Autodesk Fusion 360 part; units mm, degrees
(part 3 of 3)
component "Service_partition" placed x (1, 0, 0) y (0, 1, 0) z (0, 0, 1) at (0, 0, 0)
component "Service_floor" placed x (1, 0, 0) y (0, 1, 0) z (0, 0, 1) at (0, 0, 0)
component "Brace_lower" placed x (1, 0, 0) y (0, 1, 0) z (0, 0, 1) at (0, 0, 0)
component "Port_round_candidate" placed x (1, 0, 0) y (0, 1, 0) z (0, 0, 1) at (0, 0, 0)
component "REF_Faital_10FE200_4ohm_DATASHEET_ENVELOPE" placed x (1, 0, 0) y (0, 1, 0) z (0, 0, 1) at (0, 0, 0)
component "REF_BC_ME10V3_DATASHEET_ENVELOPE" placed x (1, 0, 0) y (0, 1, 0) z (0, 0, 1) at (0, 0, 0)
component "REF_BC_DE10_DATASHEET_ENVELOPE" placed x (1, 0, 0) y (0, 1, 0) z (0, 0, 1) at (0, 0, 0)
component "RESERVE_amp_wiring_UNVERIFIED_no_mounting_holes" placed x (1, 0, 0) y (0, 1, 0) z (0, 0, 1) at (0, 0, 0)
component "Rear_thread_plate_left_0.15" placed x (1, 0, 0) y (0, 1, 0) z (0, 0, 1) at (0, 0, 0)
component "Rear_thread_plate_left_0.5" placed x (1, 0, 0) y (0, 1, 0) z (0, 0, 1) at (0, 0, 0)
component "Rear_thread_plate_left_0.85" placed x (1, 0, 0) y (0, 1, 0) z (0, 0, 1) at (0, 0, 0)
component "Rear_thread_plate_right_0.15" placed x (1, 0, 0) y (0, 1, 0) z (0, 0, 1) at (0, 0, 0)
component "Rear_thread_plate_right_0.5" placed x (1, 0, 0) y (0, 1, 0) z (0, 0, 1) at (0, 0, 0)
component "Rear_thread_plate_right_0.85" placed x (1, 0, 0) y (0, 1, 0) z (0, 0, 1) at (0, 0, 0)
component "Rear_thread_plate_bottom_0.27" placed x (1, 0, 0) y (0, 1, 0) z (0, 0, 1) at (0, 0, 0)
component "Rear_thread_plate_bottom_0.73" placed x (1, 0, 0) y (0, 1, 0) z (0, 0, 1) at (0, 0, 0)
component "Rear_thread_plate_top_0.27" placed x (1, 0, 0) y (0, 1, 0) z (0, 0, 1) at (0, 0, 0)
component "Rear_thread_plate_top_0.73" placed x (1, 0, 0) y (0, 1, 0) z (0, 0, 1) at (0, 0, 0)
equation "height = 560 mm" comment "report:p12; envelope_not_CAD"
equation "width = 330 mm" comment "report:p12; envelope_not_CAD"
equation "depth = 300 mm" comment "report:p12; envelope_not_CAD"
equation "wall = 12 mm" comment "report:p12; design_candidate"
equation "lf_outer = 256.8 mm" comment "S31; design_candidate"
equation "lf_cutout = 233.3 mm" comment "S31; design_candidate"
equation "lf_depth = 102 mm" comment "S31; design_candidate"
equation "lf_flange = 8 mm" comment "S31; design_candidate"
equation "lf_pcd = 243.8 mm" comment "S31; design_candidate"
equation "lf_magnet_d = 115.3 mm" comment "S31:drawing_4; design_candidate"
equation "lf_magnet_depth = 34.7 mm" comment "S31:drawing_4; design_candidate"
equation "lf_basket_d = 231.8 mm" comment "S31:drawing_4; design_candidate"
equation "lf_hole_d = 5.7 mm" comment "S31:drawing_4; design_candidate"
equation "horn_width = 130.5 mm" comment "S50; design_candidate"
equation "horn_depth = 90 mm" comment "S50; design_candidate"
equation "horn_cutout = 104 mm" comment "S50:cutout_shape_to_verify; design_candidate"
equation "horn_throat = 25 mm" comment "S50; design_candidate"
equation "horn_flange = 5.5 mm" comment "S50:drawing_me10v3; manufacturer_dimension"
equation "hf_diameter = 90 mm" comment "S48; design_candidate"
equation "hf_depth = 53 mm" comment "S48; design_candidate"
equation "lf_y = 260 mm" comment "engineering:E02; design_candidate"
equation "horn_y = 470 mm" comment "engineering:E02; design_candidate"
equation "port_y = 70 mm" comment "engineering:E02; design_candidate"
equation "port_wall = 3 mm" comment "engineering:E02; design_candidate"
equation "service_floor_y = 350 mm" comment "engineering:E02; design_candidate"
equation "brace_y = 140 mm" comment "engineering:E02; design_candidate"
equation "brace_z = 200 mm" comment "engineering:E02; design_candidate"
equation "brace_height = 20 mm" comment "engineering:E02; design_candidate"
equation "baffle_clearance = 0.5 mm" comment "engineering:E02; radial_manufacturing_allowance"
equation "amp_reserve_width = 110 mm" comment "engineering:E02; unverified_installation_reserve_not_board_dimension"
equation "amp_reserve_height = 110 mm" comment "engineering:E02; unverified_installation_reserve_not_board_dimension"
equation "amp_reserve_depth = 40 mm" comment "engineering:E02; unverified_installation_reserve_not_board_dimension"
equation "rear_cleat_width = 20 mm" comment "engineering:E03; prototype_candidate_not_structurally_validated"
equation "rear_cleat_depth = 20 mm" comment "engineering:E03; prototype_candidate_not_structurally_validated"
equation "lf_backing_outer_d = 280 mm" comment "engineering:E03; prototype_candidate_not_structurally_validated"
equation "lf_backing_thickness = 3 mm" comment "engineering:E03; prototype_candidate_not_structurally_validated"
equation "lf_bolt_clearance = 5.5 mm" comment "engineering:E03; prototype_candidate_not_structurally_validated"
equation "horn_bolt_clearance = 4.5 mm" comment "engineering:E03; prototype_candidate_not_structurally_validated"
equation "horn_bolt_pitch = 114 mm" comment "S50:drawing_me10v3; manufacturer_dimension"
equation "port_backing_relief = 1 mm" comment "engineering:E03; prototype_candidate_not_structurally_validated"
equation "rear_bolt_clearance = 5.5 mm" comment "engineering:E03; prototype_candidate_not_structurally_validated"
equation "target_net = 34000000 mm^3" comment "report:p7"
equation "port_area = 6500 mm^2" comment "report:p7"
equation "port_length = 161.47860433 mm" comment "derived Helmholtz and equivalent-round end correction; prototype tune"
equation "lf_displacement = 600000 mm^3" comment "manufacturer occupied air volume, not solid clearance-envelope volume"
equation "horn_displacement = 150000 mm^3" comment "manufacturer horn volume"
equation "reinforcement_displacement = 1227503.1705 mm^3" comment "Python-derived E03 displacement"
equation "cleat_acoustic_displacement = 376800 mm^3" comment "Python-derived E03 displacement"
equation "backing_displacement = 70115.6356391 mm^3" comment "Python-derived E03 displacement"
equation "port_d = 90.9728368293 mm" comment "derived in Python; Fusion area-reference scaling workaround"
equation "service_z = 165.901490847 mm" comment "derived net-volume budget in Python; regenerate after dimensional changes"
equation "inner_width = width - 2 * wall" comment "E03 concept"
equation "inner_height = height - 2 * wall" comment "E03 concept"
equation "inner_depth = depth - 2 * wall" comment "E03 concept"
equation "port_outer_d = port_d + 2 * port_wall" comment "E03 concept"
equation "gross_internal = inner_width * inner_height * inner_depth" comment "E03 concept"
equation "port_displacement = PI / 4 * port_outer_d ^ 2 * ( port_length - 2 * wall )" comment "E03 concept"
equation "hf_displacement = PI / 4 * hf_diameter ^ 2 * hf_depth" comment "E03 concept"
equation "brace_displacement = inner_width * brace_height * wall" comment "E03 concept"
equation "service_reserve = inner_width * ( height - wall - service_floor_y ) * ( depth - wall - service_z )" comment "E03 concept"
equation "d63 = wall"
equation "d64 = height"
equation "d65 = depth"
equation "d69 = width - wall"
equation "d70 = wall"
equation "d71 = height"
equation "d72 = depth"
equation "d76 = wall"
equation "d77 = inner_width"
equation "d78 = wall"
equation "d79 = depth"
equation "d83 = wall"
equation "d84 = height - wall"
equation "d85 = inner_width"
equation "d86 = wall"
equation "d87 = depth"
equation "d91 = wall"
equation "d92 = wall"
equation "d93 = inner_width"
equation "d94 = inner_height"
equation "d95 = wall"
equation "d97 = depth - wall"
equation "d99 = wall"
equation "d100 = wall"
equation "d101 = inner_width"
equation "d102 = inner_height"
equation "d103 = wall"
equation "d107 = width / 2"
equation "d108 = lf_y"
equation "d109 = lf_cutout + 2 * baffle_clearance"
equation "d110 = wall"
equation "d114 = width / 2"
equation "d115 = port_y"
equation "d116 = port_outer_d + 2 * baffle_clearance"
equation "d117 = wall"
equation "d121 = ( width - horn_cutout ) / 2"
equation "d122 = horn_y - horn_cutout / 2"
equation "d123 = horn_cutout"
equation "d124 = horn_cutout"
equation "d125 = wall"
equation "d127 = wall"
equation "d129 = wall"
equation "d130 = wall"
equation "d131 = inner_width"
equation "d132 = inner_height"
equation "d133 = wall"
equation "d135 = wall"
equation "d137 = width / 2"
equation "d138 = lf_y"
equation "d139 = lf_cutout + 2 * baffle_clearance"
equation "d140 = wall"
equation "d142 = wall"
equation "d144 = width / 2"
equation "d145 = port_y"
equation "d146 = port_outer_d + 2 * baffle_clearance"
equation "d147 = wall"
equation "d149 = wall"
equation "d151 = ( width - horn_cutout ) / 2"
equation "d152 = horn_y - horn_cutout / 2"
equation "d153 = horn_cutout"
equation "d154 = horn_cutout"
equation "d155 = wall"
equation "d159 = width / 2 + lf_pcd / 2 * ( 1 )"
equation "d160 = lf_y + lf_pcd / 2 * ( 0 )"
equation "d161 = lf_bolt_clearance"
equation "d162 = wall"
equation "d166 = width / 2 + lf_pcd / 2 * ( 0.707106781186548 )"
equation "d167 = lf_y + lf_pcd / 2 * ( 0.707106781186548 )"
equation "d168 = lf_bolt_clearance"
equation "d169 = wall"
equation "d173 = width / 2 + lf_pcd / 2 * ( 0.000 )"
equation "d174 = lf_y + lf_pcd / 2 * ( 1 )"
equation "d175 = lf_bolt_clearance"
equation "d176 = wall"
equation "d180 = width / 2 + lf_pcd / 2 * ( -0.707106781186547 )"
equation "d181 = lf_y + lf_pcd / 2 * ( 0.707106781186548 )"
equation "d182 = lf_bolt_clearance"
equation "d183 = wall"
equation "d187 = width / 2 + lf_pcd / 2 * ( -1 )"
equation "d188 = lf_y + lf_pcd / 2 * ( 0.000 )"
equation "d189 = lf_bolt_clearance"
equation "d190 = wall"
equation "d194 = width / 2 + lf_pcd / 2 * ( -0.707106781186548 )"
equation "d195 = lf_y + lf_pcd / 2 * ( -0.707106781186547 )"
equation "d196 = lf_bolt_clearance"
equation "d197 = wall"
equation "d201 = width / 2 + lf_pcd / 2 * ( -0.000 )"
equation "d202 = lf_y + lf_pcd / 2 * ( -1 )"
equation "d203 = lf_bolt_clearance"
equation "d204 = wall"
equation "d208 = width / 2 + lf_pcd / 2 * ( 0.707106781186547 )"
equation "d209 = lf_y + lf_pcd / 2 * ( -0.707106781186548 )"
equation "d210 = lf_bolt_clearance"
equation "d211 = wall"
equation "d215 = width / 2 + ( -1 ) * horn_bolt_pitch / 2"
equation "d216 = horn_y + ( -1 ) * horn_bolt_pitch / 2"
equation "d217 = horn_bolt_clearance"
equation "d218 = wall"
equation "d222 = width / 2 + ( -1 ) * horn_bolt_pitch / 2"
equation "d223 = horn_y + ( 1 ) * horn_bolt_pitch / 2"
equation "d224 = horn_bolt_clearance"
equation "d225 = wall"
equation "d229 = width / 2 + ( 1 ) * horn_bolt_pitch / 2"
equation "d230 = horn_y + ( -1 ) * horn_bolt_pitch / 2"
equation "d231 = horn_bolt_clearance"
equation "d232 = wall"
equation "d236 = width / 2 + ( 1 ) * horn_bolt_pitch / 2"
equation "d237 = horn_y + ( 1 ) * horn_bolt_pitch / 2"
equation "d238 = horn_bolt_clearance"
equation "d239 = wall"
equation "d241 = wall"
equation "d243 = width / 2 + lf_pcd / 2 * ( 1 )"
equation "d244 = lf_y + lf_pcd / 2 * ( 0 )"
equation "d245 = lf_bolt_clearance"
equation "d246 = wall"
equation "d248 = wall"
equation "d250 = width / 2 + lf_pcd / 2 * ( 0.707106781186548 )"
equation "d251 = lf_y + lf_pcd / 2 * ( 0.707106781186548 )"
equation "d252 = lf_bolt_clearance"
equation "d253 = wall"
equation "d255 = wall"
equation "d257 = width / 2 + lf_pcd / 2 * ( 0.000 )"
equation "d258 = lf_y + lf_pcd / 2 * ( 1 )"
equation "d259 = lf_bolt_clearance"
equation "d260 = wall"
equation "d262 = wall"
equation "d264 = width / 2 + lf_pcd / 2 * ( -0.707106781186547 )"
equation "d265 = lf_y + lf_pcd / 2 * ( 0.707106781186548 )"
equation "d266 = lf_bolt_clearance"
equation "d267 = wall"
equation "d269 = wall"
equation "d271 = width / 2 + lf_pcd / 2 * ( -1 )"
equation "d272 = lf_y + lf_pcd / 2 * ( 0.000 )"
equation "d273 = lf_bolt_clearance"
equation "d274 = wall"
equation "d276 = wall"
equation "d278 = width / 2 + lf_pcd / 2 * ( -0.707106781186548 )"
equation "d279 = lf_y + lf_pcd / 2 * ( -0.707106781186547 )"
equation "d280 = lf_bolt_clearance"
equation "d281 = wall"
equation "d283 = wall"
equation "d285 = width / 2 + lf_pcd / 2 * ( -0.000 )"
equation "d286 = lf_y + lf_pcd / 2 * ( -1 )"
equation "d287 = lf_bolt_clearance"
equation "d288 = wall"
equation "d290 = wall"
equation "d292 = width / 2 + lf_pcd / 2 * ( 0.707106781186547 )"
equation "d293 = lf_y + lf_pcd / 2 * ( -0.707106781186548 )"
equation "d294 = lf_bolt_clearance"
equation "d295 = wall"
equation "d297 = wall"
equation "d299 = width / 2 + ( -1 ) * horn_bolt_pitch / 2"
equation "d300 = horn_y + ( -1 ) * horn_bolt_pitch / 2"
equation "d301 = horn_bolt_clearance"
equation "d302 = wall"
equation "d304 = wall"
equation "d306 = width / 2 + ( -1 ) * horn_bolt_pitch / 2"
equation "d307 = horn_y + ( 1 ) * horn_bolt_pitch / 2"
equation "d308 = horn_bolt_clearance"
equation "d309 = wall"
equation "d311 = wall"
equation "d313 = width / 2 + ( 1 ) * horn_bolt_pitch / 2"
equation "d314 = horn_y + ( -1 ) * horn_bolt_pitch / 2"
equation "d315 = horn_bolt_clearance"
equation "d316 = wall"
equation "d318 = wall"
equation "d320 = width / 2 + ( 1 ) * horn_bolt_pitch / 2"
equation "d321 = horn_y + ( 1 ) * horn_bolt_pitch / 2"
equation "d322 = horn_bolt_clearance"
equation "d323 = wall"
equation "d325 = 2 * wall"
equation "d327 = width / 2"
equation "d328 = lf_y"
equation "d329 = lf_backing_outer_d"
equation "d330 = lf_backing_inner_d"
equation "d331 = lf_backing_thickness"
equation "d333 = 2 * wall"
equation "d335 = width / 2"
equation "d336 = port_y"
equation "d337 = port_outer_d + 2 * port_backing_relief"
equation "d340 = 2 * wall"
equation "d342 = width / 2 + lf_pcd / 2 * ( 1 )"
equation "d343 = lf_y + lf_pcd / 2 * ( 0 )"
equation "d344 = lf_bolt_clearance"
equation "d345 = lf_backing_thickness"
equation "d347 = 2 * wall"
equation "d349 = width / 2 + lf_pcd / 2 * ( 0.707106781186548 )"
equation "d350 = lf_y + lf_pcd / 2 * ( 0.707106781186548 )"
equation "d351 = lf_bolt_clearance"
equation "d352 = lf_backing_thickness"
equation "d354 = 2 * wall"
equation "d356 = width / 2 + lf_pcd / 2 * ( 0.000 )"
equation "d357 = lf_y + lf_pcd / 2 * ( 1 )"
equation "d358 = lf_bolt_clearance"
equation "d359 = lf_backing_thickness"
equation "d361 = 2 * wall"
equation "d363 = width / 2 + lf_pcd / 2 * ( -0.707106781186547 )"
equation "d364 = lf_y + lf_pcd / 2 * ( 0.707106781186548 )"
equation "d365 = lf_bolt_clearance"
equation "d366 = lf_backing_thickness"
equation "d368 = 2 * wall"
equation "d370 = width / 2 + lf_pcd / 2 * ( -1 )"
equation "d371 = lf_y + lf_pcd / 2 * ( 0.000 )"
equation "d372 = lf_bolt_clearance"
equation "d373 = lf_backing_thickness"
equation "d375 = 2 * wall"
equation "d377 = width / 2 + lf_pcd / 2 * ( -0.707106781186548 )"
equation "d378 = lf_y + lf_pcd / 2 * ( -0.707106781186547 )"
equation "d379 = lf_bolt_clearance"
equation "d380 = lf_backing_thickness"
equation "d382 = 2 * wall"
equation "d384 = width / 2 + lf_pcd / 2 * ( -0.000 )"
equation "d385 = lf_y + lf_pcd / 2 * ( -1 )"
equation "d386 = lf_bolt_clearance"
equation "d387 = lf_backing_thickness"
equation "d389 = 2 * wall"
equation "d391 = width / 2 + lf_pcd / 2 * ( 0.707106781186547 )"
equation "d392 = lf_y + lf_pcd / 2 * ( -0.707106781186548 )"
equation "d393 = lf_bolt_clearance"
equation "d394 = lf_backing_thickness"
equation "d396 = depth - wall - rear_cleat_depth"
equation "d398 = wall"
equation "d399 = wall"
equation "d400 = rear_cleat_width"
equation "d401 = inner_height"
equation "d402 = rear_cleat_depth"
equation "d404 = depth - wall - rear_cleat_depth"
equation "d406 = width - wall - rear_cleat_width"
equation "d407 = wall"
equation "d408 = rear_cleat_width"
equation "d409 = inner_height"
equation "d410 = rear_cleat_depth"
equation "d412 = depth - wall - rear_cleat_depth"
equation "d414 = wall + rear_cleat_width"
equation "d415 = wall"
equation "d416 = inner_width - 2 * rear_cleat_width"
equation "d417 = rear_cleat_width"
equation "d418 = rear_cleat_depth"
equation "d420 = depth - wall - rear_cleat_depth"
equation "d422 = wall + rear_cleat_width"
equation "d423 = height - wall - rear_cleat_width"
equation "d424 = inner_width - 2 * rear_cleat_width"
equation "d425 = rear_cleat_width"
equation "d426 = rear_cleat_depth"
equation "d428 = service_z"
equation "d430 = wall"
equation "d431 = service_floor_y + wall"
equation "d432 = inner_width"
equation "d433 = height - wall - service_floor_y - wall"
equation "d434 = wall"
equation "d436 = service_z"
equation "d438 = wall"
equation "d439 = service_floor_y"
equation "d440 = inner_width"
equation "d441 = wall"
equation "d442 = depth - wall - service_z"
equation "d444 = brace_z"
equation "d446 = wall"
equation "d447 = brace_y"
equation "d448 = inner_width"
equation "d449 = brace_height"
equation "d450 = wall"
equation "d454 = width / 2"
equation "d455 = port_y"
equation "d456 = port_outer_d"
equation "d457 = port_d"
equation "d458 = port_length"
equation "d460 = -lf_flange"
equation "d462 = width / 2"
equation "d463 = lf_y"
equation "d464 = lf_outer"
equation "d465 = lf_cutout"
equation "d466 = lf_flange"
equation "d470 = width / 2"
equation "d471 = lf_y"
equation "d472 = lf_basket_d"
equation "d473 = lf_depth - lf_flange - lf_magnet_depth"
equation "d475 = width / 2"
equation "d476 = lf_y"
equation "d477 = lf_magnet_d"
equation "d478 = lf_depth - lf_flange - lf_magnet_depth"
equation "d480 = width / 2"
equation "d481 = lf_y"
equation "d482 = lf_magnet_d"
equation "d483 = lf_magnet_depth"
equation "d485 = -horn_flange"
equation "d487 = ( width - horn_width ) / 2"
equation "d488 = horn_y - horn_width / 2"
equation "d489 = horn_width"
equation "d490 = horn_width"
equation "d491 = horn_flange"
equation "d493 = -horn_flange"
equation "d495 = ( width - horn_cutout ) / 2"
equation "d496 = horn_y - horn_cutout / 2"
equation "d497 = horn_cutout"
equation "d498 = horn_cutout"
equation "d499 = horn_flange"
equation "d503 = ( width - horn_cutout ) / 2"
equation "d504 = horn_y - horn_cutout / 2"
equation "d505 = horn_cutout"
equation "d506 = horn_cutout"
equation "d507 = horn_depth - horn_flange"
equation "d509 = width / 2"
equation "d510 = horn_y"
equation "d511 = horn_throat"
equation "d512 = horn_depth - horn_flange"
equation "d514 = width / 2"
equation "d515 = horn_y"
equation "d516 = hf_diameter"
equation "d517 = hf_depth"
equation "d519 = service_z + wall + 10 mm"
equation "d521 = ( width - amp_reserve_width ) / 2"
equation "d522 = service_floor_y + wall + 10 mm"
equation "d523 = amp_reserve_width"
equation "d524 = amp_reserve_height"
equation "d525 = amp_reserve_depth"
equation "d527 = depth - wall - rear_cleat_depth"
equation "d533 = depth - wall - rear_cleat_depth"
equation "rear_plate_width = 20 mm" comment "engineering:E03_assembly"
equation "rear_plate_length = 40 mm" comment "engineering:E03_assembly"
equation "rear_plate_thickness = 5 mm" comment "engineering:E03_assembly"
equation "rear_tap_pilot = 4.2 mm" comment "engineering:E03_assembly"
equation "rear_retainer_bore = 3 mm" comment "engineering:E03_assembly"
equation "rear_retainer_pitch = 24 mm" comment "engineering:E03_assembly"
equation "gasket_groove_width = 4 mm" comment "engineering:E03_assembly"
equation "gasket_groove_depth = 1 mm" comment "engineering:E03_assembly"
equation "gasket_edge_offset = 2 mm" comment "engineering:E03_assembly"
equation "rear_fixing_displacement = 20309.2569506 mm^3" comment "Python-derived volume budget"
equation "d549 = depth - wall"
equation "d551 = wall + rear_cleat_width / 2"
equation "d552 = height * 0.15"
equation "d553 = rear_bolt_clearance"
equation "d554 = wall"
equation "d556 = depth - wall - rear_cleat_depth"
equation "d558 = wall + rear_cleat_width / 2"
equation "d559 = height * 0.15"
equation "d560 = rear_bolt_clearance"
equation "d563 = depth - wall - rear_cleat_depth - rear_plate_thickness"
equation "d565 = ( wall + rear_cleat_width / 2 ) - ( rear_plate_width ) / 2"
equation "d566 = ( height * 0.15 ) - ( rear_plate_length ) / 2"
equation "d567 = rear_plate_width"
equation "d568 = rear_plate_length"
equation "d569 = rear_plate_thickness"
equation "d571 = depth - wall - rear_cleat_depth - rear_plate_thickness"
equation "d573 = wall + rear_cleat_width / 2"
equation "d574 = height * 0.15"
equation "d575 = rear_tap_pilot"
equation "d576 = rear_plate_thickness"
equation "d578 = depth - wall - rear_cleat_depth - rear_plate_thickness"
equation "d580 = wall + rear_cleat_width / 2"
equation "d581 = ( height * 0.15 ) + ( -1 ) * rear_retainer_pitch / 2"
equation "d582 = rear_retainer_bore"
equation "d583 = rear_plate_thickness"
equation "d585 = depth - wall - rear_cleat_depth - rear_plate_thickness"
equation "d587 = wall + rear_cleat_width / 2"
equation "d588 = ( height * 0.15 ) + ( 1 ) * rear_retainer_pitch / 2"
equation "d589 = rear_retainer_bore"
equation "d590 = rear_plate_thickness"
equation "d592 = depth - wall"
equation "d594 = wall + rear_cleat_width / 2"
equation "d595 = height * 0.5"
equation "d596 = rear_bolt_clearance"
equation "d597 = wall"
equation "d599 = depth - wall - rear_cleat_depth"
equation "d601 = wall + rear_cleat_width / 2"
equation "d602 = height * 0.5"
equation "d603 = rear_bolt_clearance"
equation "d606 = depth - wall - rear_cleat_depth - rear_plate_thickness"
equation "d608 = ( wall + rear_cleat_width / 2 ) - ( rear_plate_width ) / 2"
equation "d609 = ( height * 0.5 ) - ( rear_plate_length ) / 2"
equation "d610 = rear_plate_width"
equation "d611 = rear_plate_length"
equation "d612 = rear_plate_thickness"
equation "d614 = depth - wall - rear_cleat_depth - rear_plate_thickness"
equation "d616 = wall + rear_cleat_width / 2"
equation "d617 = height * 0.5"
equation "d618 = rear_tap_pilot"
equation "d619 = rear_plate_thickness"
equation "d621 = depth - wall - rear_cleat_depth - rear_plate_thickness"
equation "d623 = wall + rear_cleat_width / 2"
equation "d624 = ( height * 0.5 ) + ( -1 ) * rear_retainer_pitch / 2"
equation "d625 = rear_retainer_bore"
equation "d626 = rear_plate_thickness"
equation "d628 = depth - wall - rear_cleat_depth - rear_plate_thickness"
equation "d630 = wall + rear_cleat_width / 2"
equation "d631 = ( height * 0.5 ) + ( 1 ) * rear_retainer_pitch / 2"
equation "d632 = rear_retainer_bore"
equation "d633 = rear_plate_thickness"
equation "d635 = depth - wall"
equation "d637 = wall + rear_cleat_width / 2"
equation "d638 = height * 0.85"
equation "d639 = rear_bolt_clearance"
equation "d640 = wall"
equation "d642 = depth - wall - rear_cleat_depth"
equation "d644 = wall + rear_cleat_width / 2"
equation "d645 = height * 0.85"
equation "d646 = rear_bolt_clearance"
equation "d649 = depth - wall - rear_cleat_depth - rear_plate_thickness"
equation "d651 = ( wall + rear_cleat_width / 2 ) - ( rear_plate_width ) / 2"
equation "d652 = ( height * 0.85 ) - ( rear_plate_length ) / 2"
equation "d653 = rear_plate_width"
equation "d654 = rear_plate_length"
equation "d655 = rear_plate_thickness"
equation "d657 = depth - wall - rear_cleat_depth - rear_plate_thickness"
equation "d659 = wall + rear_cleat_width / 2"
equation "d660 = height * 0.85"
equation "d661 = rear_tap_pilot"
equation "d662 = rear_plate_thickness"
equation "d664 = depth - wall - rear_cleat_depth - rear_plate_thickness"
equation "d666 = wall + rear_cleat_width / 2"
equation "d667 = ( height * 0.85 ) + ( -1 ) * rear_retainer_pitch / 2"
equation "d668 = rear_retainer_bore"
equation "d669 = rear_plate_thickness"
equation "d671 = depth - wall - rear_cleat_depth - rear_plate_thickness"
equation "d673 = wall + rear_cleat_width / 2"
equation "d674 = ( height * 0.85 ) + ( 1 ) * rear_retainer_pitch / 2"
equation "d675 = rear_retainer_bore"
equation "d676 = rear_plate_thickness"
equation "d678 = depth - wall"
equation "d680 = width - wall - rear_cleat_width / 2"
equation "d681 = height * 0.15"
equation "d682 = rear_bolt_clearance"
equation "d683 = wall"
equation "d685 = depth - wall - rear_cleat_depth"
equation "d687 = width - wall - rear_cleat_width / 2"
equation "d688 = height * 0.15"
equation "d689 = rear_bolt_clearance"
equation "d692 = depth - wall - rear_cleat_depth - rear_plate_thickness"
equation "d694 = ( width - wall - rear_cleat_width / 2 ) - ( rear_plate_width ) / 2"
equation "d695 = ( height * 0.15 ) - ( rear_plate_length ) / 2"
equation "d696 = rear_plate_width"
equation "d697 = rear_plate_length"
equation "d698 = rear_plate_thickness"
equation "d700 = depth - wall - rear_cleat_depth - rear_plate_thickness"
equation "d702 = width - wall - rear_cleat_width / 2"
equation "d703 = height * 0.15"
equation "d704 = rear_tap_pilot"
equation "d705 = rear_plate_thickness"
equation "d707 = depth - wall - rear_cleat_depth - rear_plate_thickness"
equation "d709 = width - wall - rear_cleat_width / 2"
equation "d710 = ( height * 0.15 ) + ( -1 ) * rear_retainer_pitch / 2"
equation "d711 = rear_retainer_bore"
equation "d712 = rear_plate_thickness"
equation "d714 = depth - wall - rear_cleat_depth - rear_plate_thickness"
equation "d716 = width - wall - rear_cleat_width / 2"
equation "d717 = ( height * 0.15 ) + ( 1 ) * rear_retainer_pitch / 2"
equation "d718 = rear_retainer_bore"
equation "d719 = rear_plate_thickness"
equation "d721 = depth - wall"
equation "d723 = width - wall - rear_cleat_width / 2"
equation "d724 = height * 0.5"
equation "d725 = rear_bolt_clearance"
equation "d726 = wall"
equation "d728 = depth - wall - rear_cleat_depth"
equation "d730 = width - wall - rear_cleat_width / 2"
equation "d731 = height * 0.5"
equation "d732 = rear_bolt_clearance"
equation "d735 = depth - wall - rear_cleat_depth - rear_plate_thickness"
equation "d737 = ( width - wall - rear_cleat_width / 2 ) - ( rear_plate_width ) / 2"
equation "d738 = ( height * 0.5 ) - ( rear_plate_length ) / 2"
equation "d739 = rear_plate_width"
equation "d740 = rear_plate_length"
equation "d741 = rear_plate_thickness"
equation "d743 = depth - wall - rear_cleat_depth - rear_plate_thickness"
equation "d745 = width - wall - rear_cleat_width / 2"
equation "d746 = height * 0.5"
equation "d747 = rear_tap_pilot"
equation "d748 = rear_plate_thickness"
equation "d750 = depth - wall - rear_cleat_depth - rear_plate_thickness"
equation "d752 = width - wall - rear_cleat_width / 2"
equation "d753 = ( height * 0.5 ) + ( -1 ) * rear_retainer_pitch / 2"
equation "d754 = rear_retainer_bore"
equation "d755 = rear_plate_thickness"
equation "d757 = depth - wall - rear_cleat_depth - rear_plate_thickness"
equation "d759 = width - wall - rear_cleat_width / 2"
equation "d760 = ( height * 0.5 ) + ( 1 ) * rear_retainer_pitch / 2"
equation "d761 = rear_retainer_bore"
equation "d762 = rear_plate_thickness"
equation "d764 = depth - wall"
equation "d766 = width - wall - rear_cleat_width / 2"
equation "d767 = height * 0.85"
equation "d768 = rear_bolt_clearance"
equation "d769 = wall"
equation "d771 = depth - wall - rear_cleat_depth"
equation "d773 = width - wall - rear_cleat_width / 2"
equation "d774 = height * 0.85"
equation "d775 = rear_bolt_clearance"
equation "d778 = depth - wall - rear_cleat_depth - rear_plate_thickness"
equation "d780 = ( width - wall - rear_cleat_width / 2 ) - ( rear_plate_width ) / 2"
equation "d781 = ( height * 0.85 ) - ( rear_plate_length ) / 2"
equation "d782 = rear_plate_width"
equation "d783 = rear_plate_length"
equation "d784 = rear_plate_thickness"
equation "d786 = depth - wall - rear_cleat_depth - rear_plate_thickness"
equation "d788 = width - wall - rear_cleat_width / 2"
equation "d789 = height * 0.85"
equation "d790 = rear_tap_pilot"
equation "d791 = rear_plate_thickness"
equation "d793 = depth - wall - rear_cleat_depth - rear_plate_thickness"
equation "d795 = width - wall - rear_cleat_width / 2"
equation "d796 = ( height * 0.85 ) + ( -1 ) * rear_retainer_pitch / 2"
equation "d797 = rear_retainer_bore"
equation "d798 = rear_plate_thickness"
equation "d800 = depth - wall - rear_cleat_depth - rear_plate_thickness"
equation "d802 = width - wall - rear_cleat_width / 2"
equation "d803 = ( height * 0.85 ) + ( 1 ) * rear_retainer_pitch / 2"
equation "d804 = rear_retainer_bore"
equation "d805 = rear_plate_thickness"
equation "d807 = depth - wall"
equation "d809 = width * 0.27"
equation "d810 = wall + rear_cleat_width / 2"
equation "d811 = rear_bolt_clearance"
equation "d812 = wall"
equation "d814 = depth - wall - rear_cleat_depth"
equation "d816 = width * 0.27"
equation "d817 = wall + rear_cleat_width / 2"
equation "d818 = rear_bolt_clearance"
equation "d819 = rear_cleat_depth"
equation "d821 = depth - wall - rear_cleat_depth - rear_plate_thickness"
equation "d823 = ( width * 0.27 ) - ( rear_plate_length ) / 2"
equation "d824 = ( wall + rear_cleat_width / 2 ) - ( rear_plate_width ) / 2"
equation "d825 = rear_plate_length"
equation "d826 = rear_plate_width"
equation "d827 = rear_plate_thickness"
equation "d829 = depth - wall - rear_cleat_depth - rear_plate_thickness"
equation "d831 = width * 0.27"
equation "d832 = wall + rear_cleat_width / 2"
equation "d833 = rear_tap_pilot"
equation "d834 = rear_plate_thickness"
equation "d836 = depth - wall - rear_cleat_depth - rear_plate_thickness"
equation "d838 = ( width * 0.27 ) + ( -1 ) * rear_retainer_pitch / 2"
equation "d839 = wall + rear_cleat_width / 2"
equation "d840 = rear_retainer_bore"
equation "d841 = rear_plate_thickness"
equation "d843 = depth - wall - rear_cleat_depth - rear_plate_thickness"
equation "d845 = ( width * 0.27 ) + ( 1 ) * rear_retainer_pitch / 2"
equation "d846 = wall + rear_cleat_width / 2"
equation "d847 = rear_retainer_bore"
equation "d848 = rear_plate_thickness"
equation "d850 = depth - wall"
equation "d852 = width * 0.73"
equation "d853 = wall + rear_cleat_width / 2"
equation "d854 = rear_bolt_clearance"
equation "d855 = wall"
equation "d857 = depth - wall - rear_cleat_depth"
equation "d859 = width * 0.73"
equation "d860 = wall + rear_cleat_width / 2"
equation "d861 = rear_bolt_clearance"
equation "d862 = rear_cleat_depth"
equation "d864 = depth - wall - rear_cleat_depth - rear_plate_thickness"
equation "d866 = ( width * 0.73 ) - ( rear_plate_length ) / 2"
equation "d867 = ( wall + rear_cleat_width / 2 ) - ( rear_plate_width ) / 2"
equation "d868 = rear_plate_length"
equation "d869 = rear_plate_width"
equation "d870 = rear_plate_thickness"
equation "d872 = depth - wall - rear_cleat_depth - rear_plate_thickness"
equation "d874 = width * 0.73"
equation "d875 = wall + rear_cleat_width / 2"
equation "d876 = rear_tap_pilot"
equation "d877 = rear_plate_thickness"
equation "d879 = depth - wall - rear_cleat_depth - rear_plate_thickness"
equation "d881 = ( width * 0.73 ) + ( -1 ) * rear_retainer_pitch / 2"
equation "d882 = wall + rear_cleat_width / 2"
equation "d883 = rear_retainer_bore"
equation "d884 = rear_plate_thickness"
equation "d886 = depth - wall - rear_cleat_depth - rear_plate_thickness"
equation "d888 = ( width * 0.73 ) + ( 1 ) * rear_retainer_pitch / 2"
equation "d889 = wall + rear_cleat_width / 2"
equation "d890 = rear_retainer_bore"
equation "d891 = rear_plate_thickness"
equation "d893 = depth - wall"
equation "d895 = width * 0.27"
equation "d896 = height - wall - rear_cleat_width / 2"
equation "d897 = rear_bolt_clearance"
equation "d898 = wall"
equation "d900 = depth - wall - rear_cleat_depth"
equation "d902 = width * 0.27"
equation "d903 = height - wall - rear_cleat_width / 2"
equation "d904 = rear_bolt_clearance"
equation "d905 = rear_cleat_depth"
equation "d907 = depth - wall - rear_cleat_depth - rear_plate_thickness"
equation "d909 = ( width * 0.27 ) - ( rear_plate_length ) / 2"
equation "d910 = ( height - wall - rear_cleat_width / 2 ) - ( rear_plate_width ) / 2"
equation "d911 = rear_plate_length"
equation "d912 = rear_plate_width"
equation "d913 = rear_plate_thickness"
equation "d915 = depth - wall - rear_cleat_depth - rear_plate_thickness"
equation "d917 = width * 0.27"
equation "d918 = height - wall - rear_cleat_width / 2"
equation "d919 = rear_tap_pilot"
equation "d920 = rear_plate_thickness"
equation "d922 = depth - wall - rear_cleat_depth - rear_plate_thickness"
equation "d924 = ( width * 0.27 ) + ( -1 ) * rear_retainer_pitch / 2"
equation "d925 = height - wall - rear_cleat_width / 2"
equation "d926 = rear_retainer_bore"
equation "d927 = rear_plate_thickness"
equation "d929 = depth - wall - rear_cleat_depth - rear_plate_thickness"
equation "d931 = ( width * 0.27 ) + ( 1 ) * rear_retainer_pitch / 2"
equation "d932 = height - wall - rear_cleat_width / 2"
equation "d933 = rear_retainer_bore"
equation "d934 = rear_plate_thickness"
equation "d936 = depth - wall"
equation "d938 = width * 0.73"
equation "d939 = height - wall - rear_cleat_width / 2"
equation "d940 = rear_bolt_clearance"
equation "d941 = wall"
equation "d943 = depth - wall - rear_cleat_depth"
equation "d945 = width * 0.73"
equation "d946 = height - wall - rear_cleat_width / 2"
equation "d947 = rear_bolt_clearance"
equation "d948 = rear_cleat_depth"
equation "d950 = depth - wall - rear_cleat_depth - rear_plate_thickness"
equation "d952 = ( width * 0.73 ) - ( rear_plate_length ) / 2"
equation "d953 = ( height - wall - rear_cleat_width / 2 ) - ( rear_plate_width ) / 2"
equation "d954 = rear_plate_length"
equation "d955 = rear_plate_width"
equation "d956 = rear_plate_thickness"
equation "d958 = depth - wall - rear_cleat_depth - rear_plate_thickness"
equation "d960 = width * 0.73"
equation "d961 = height - wall - rear_cleat_width / 2"
equation "d962 = rear_tap_pilot"
equation "d963 = rear_plate_thickness"
equation "d965 = depth - wall - rear_cleat_depth - rear_plate_thickness"
equation "d967 = ( width * 0.73 ) + ( -1 ) * rear_retainer_pitch / 2"
equation "d968 = height - wall - rear_cleat_width / 2"
equation "d969 = rear_retainer_bore"
equation "d970 = rear_plate_thickness"
equation "d972 = depth - wall - rear_cleat_depth - rear_plate_thickness"
equation "d974 = ( width * 0.73 ) + ( 1 ) * rear_retainer_pitch / 2"
equation "d975 = height - wall - rear_cleat_width / 2"
equation "d976 = rear_retainer_bore"
equation "d977 = rear_plate_thickness"
equation "d979 = depth - wall"
equation "d981 = gasket_groove_depth"
equation "lf_backing_inner_d = 220 mm" comment "engineering:E03_bearing_margin"
equation "d984 = rear_cleat_depth"
equation "d986 = rear_cleat_depth"
named bodies: "Side_left", "Side_right", "Bottom", "Top", "Baffle", "Rear_removable", "Baffle_inner_lamination", "Steel_backing_ring", "Rear_cleat_left", "Rear_cleat_right", "Rear_cleat_bottom", "Rear_cleat_top", "Service_partition", "Service_floor", "Brace_lower", "Port_tube", "LF_flange_envelope", "Magnet_envelope", "Horn_flange_envelope", "DE10_cylinder_envelope", "Amp_space_reserve", "Steel_plate_M5_tap_after_drilling"
